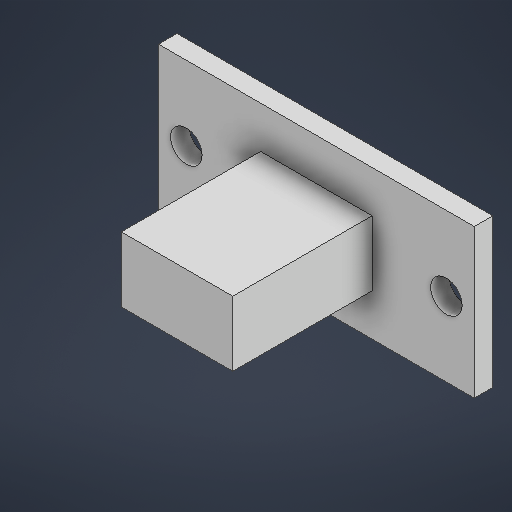
# Autodesk Inventor part: DUMMY-USB
Saved by Autodesk Inventor 2027.1 (Build 311270010, 270A)
## iProperties
Created: 2026-10-28
Part Number: DUMMY-USB
Material: Generic
Description: USB panel socket
Document SubType Name: Modeling
Designer: shyan
Mass: 5 g
Density: 1 g/cm^3
Appearance: Default
Author: shyan
Autodesk Inventor part; units mm, degrees
ref_plane "YZ Plane" through (0, 0, 0) normal (1, 0, 0) x (0, 1, 0)
ref_plane "XZ Plane" through (0, 0, 0) normal (0, 1, 0) x (-1, 0, 0)
sketch "sk_flange" plane through (0, 0, 0) normal (0, 0, 1) x (1, 0, 0)
  line L0 (0, 0) -> (50, 0) construction
  line L1 (0, 0) -> (0, 50) construction
  line L2 (-17, -8) -> (17, -8)
  line L3 (17, -8) -> (17, 8)
  line L4 (17, 8) -> (-17, 8)
  line L5 (-17, 8) -> (-17, -8)
  dimension "d0" = 34
  dimension "d1" = 16
  constraints: 12 end point, 2 parallel, 1 horizontal, 1 perpendicular, 6 other
  measures "d0" distance of L2.start L2.end
  measures "d1" distance of L2.end L3.end
extrude "Flange" add sketch "sk_flange" along normal blind 2
ref_plane "sk_barrel_plane" through (0, 0, 2) normal (0, 0, 1) x (1, 0, 0)
sketch "sk_barrel" plane through (0, 0, 2) normal (0, 0, 1) x (1, 0, 0)
  line L0 (0, 0) -> (50, 0) construction
  line L1 (0, 0) -> (0, 50) construction
  line L2 (-6, -3.5) -> (6, -3.5)
  line L3 (6, -3.5) -> (6, 3.5)
  line L4 (6, 3.5) -> (-6, 3.5)
  line L5 (-6, 3.5) -> (-6, -3.5)
  dimension "d5" = 12
  dimension "d6" = 7
  constraints: 12 end point, 2 parallel, 1 horizontal, 1 perpendicular, 6 other
  measures "d5" distance of L2.start L2.end
  measures "d6" distance of L2.end L3.end
extrude "Barrel" add sketch "sk_barrel" along normal blind 15
sketch "sk_screws" plane through (0, 0, 0) normal (0, 0, 1) x (1, 0, 0)
  line L0 (0, 0) -> (50, 0) construction
  line L1 (0, 0) -> (0, 50) construction
  circle A0 centre (14, 0) radius 1.7
  circle A1 centre (-14, 0) radius 1.7
  dimension "d9" = 3.4
  dimension "d10" = 14
  dimension "d11" = 3.4
  dimension "d12" = 14
  constraints: 4 end point, 2 centre point, 2 point on line, 4 other
  measures "d9" diameter of A0
  measures "d10" distance of L0.start A0.centre
  measures "d11" diameter of A1
  measures "d12" distance of L0.start A1.centre
extrude "ScrewHoles" cut sketch "sk_screws" along normal blind 2
equation "\"d0\" = usb_fl_W"
equation "\"d1\" = usb_fl_H"
equation "\"d2\" = usb_fl_T"
equation "\"d5\" = usb_cut_W"
equation "\"d6\" = usb_cut_H"
equation "\"d7\" = usb_body_L"
equation "\"d9\" = m3"
equation "\"d10\" = 0.5 * usb_pitch"
equation "\"d11\" = m3"
equation "\"d12\" = 0.5 * usb_pitch"
equation "\"d13\" = usb_fl_T"
equation "\"usb_fl_W\" = 34"
equation "\"usb_fl_H\" = 16"
equation "\"usb_fl_T\" = 2"
equation "\"usb_cut_W\" = 12"
equation "\"usb_cut_H\" = 7"
equation "\"usb_body_L\" = 15"
equation "\"usb_pitch\" = 28"
equation "\"m3\" = 3.4"
equation "\"d4\" = usb_fl_T"
body "Solid1"
